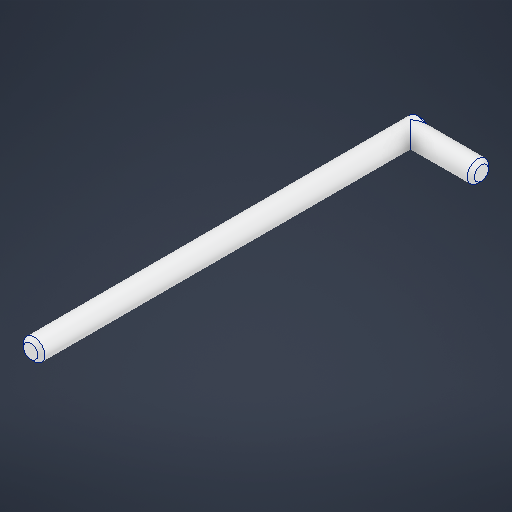
# Autodesk Inventor part: shaft
Saved by Autodesk Inventor 2027.1 (Build 311270010, 270A)
## iProperties
Created: 2026-10-16
Part Number: shaft
Material: Aluminum 6061
Document SubType Name: Modeling
Designer: youss
Density: 2.7 g/cm^3
Appearance: Aluminum - Flat
Author: youss
Autodesk Inventor part; units mm, degrees
ref_plane "YZ Plane" through (0, 0, 0) normal (1, 0, 0) x (0, 1, 0)
ref_plane "XZ Plane" through (0, 0, 0) normal (0, 1, 0) x (-1, 0, 0)
ref_plane "XY Plane" through (0, 0, 0) normal (0, 0, 1) x (1, 0, 0)
sketch "Sketch1" plane through (0, 0, 0) normal (0, 0, 1) x (1, 0, 0)
  circle A0 centre (0, 0) radius 3
  dimension "d0" = 6
  constraints: 1 centre point, 1 coincident
  measures "d0" diameter of A0
extrude "Extrusion1" add sketch "Sketch1" along normal blind 110
chamfer "Chamfer1" distance 1 angle 45 2 edges at (-3, 0, 110) (-3, 0, 0)
sketch "Sketch2" plane through (0, 0, 0) normal (1, 0, 0) x (0, 1, 0)
  circle A0 centre (0, 3) radius 3
  line L0 (3, 109) -> (-3, 109) projected
  line L1 (-3, 1) -> (3, 1) projected
  line L2 (2, 0) -> (-2, 0) projected
  line L3 (-3, 1) -> (3, 1) projected
  line L4 (2, 0) -> (-2, 0) projected
  line L5 (-3, 1) -> (-3, 109) projected
  point P0 (0, 0)
  dimension "d6" = 6
  constraints: 2 tangent, 1 centre point
  measures "d6" diameter of A0
extrude "Extrusion2" add sketch "Sketch2" along normal blind 20 contours A0 L1 | A0 L1
chamfer "Chamfer2" distance 1 angle 45 1 edges at (20, -3, 3)
body "Solid1"
